211402_P01_WALL-SKIN-BACK-LOWER-B2_CAD (Autodesk Fusion 360 design; units mm, degrees)
part number: 2026-11-02-10-36-47-866
description: WALL - SKIN - BACK LOWER - B2 | Vách hậu - tấm ốp alu dưới phải | P01
part number: 211402
Autodesk Fusion 360 part; units mm, degrees
ref_plane "WorkPlane1" through (0, 0, 112.26) normal (0, 0, 1) x (1, 0, 0) in component "211402 WALL - SKIN - BACK LOWER - B2"
sketch "SKETCH - SKIN PLATE" plane through (0, 0, 112.26) normal (0, 0, 1) x (1, 0, 0) in component "211402 WALL - SKIN - BACK LOWER - B2"
  line L0 (1.13, 847) -> (1201.74, 847)
  line L1 (1201.74, 847) -> (1201.74, 850)
  line L2 (1201.74, 850) -> (1.13, 850)
  line L3 (1.13, 850) -> (1.13, 847)
  dimension "d218" = 1200.61
  dimension "d219" = 3
  dimension "d220" = 1.13
  dimension "d221" = 847
  constraint horizontal L0
  constraint vertical L1
  constraint horizontal L2
  constraint vertical L3
  measures "d218" horizontal distance of L0.start L0.end
  measures "d219" vertical distance of L0.start L2.end
  measures "d220" horizontal distance of origin L0.start
  measures "d221" vertical distance of origin L0.start
extrude "EXTRUDE - SKIN PLATE" add sketch "SKETCH - SKIN PLATE" along normal blind 1118.61 in component "211402 WALL - SKIN - BACK LOWER - B2"
ref_plane "WorkPlane2" through (0, 850, 0) normal (0, 1, 0) x (0, 0, 1) in component "211402 WALL - SKIN - BACK LOWER - B2"
sketch "HOLE CENTRE - SKIN MAINS INLET" plane through (0, 850, 0) normal (0, 1, 0) x (1, 0, 0) in component "211402 WALL - SKIN - BACK LOWER - B2"
  point P0 (120, -313)
  dimension "d226" = 120
  dimension "d227" = 313
  measures "d226" horizontal distance of origin P0
  measures "d227" vertical distance of origin P0
hole "HOLE - SKIN MAINS INLET" at (120, 850, 313) direction (0, -1, 0) diameter 24 depth 4 tip angle 118 in component "211402 WALL - SKIN - BACK LOWER - B2"
ref_plane "WorkPlane3" through (0, 850, 0) normal (0, 1, 0) x (0, 0, 1) in component "211402 WALL - SKIN - BACK LOWER - B2"
sketch "HOLE CENTRE - SKIN MAINS INLET SCREW 1" plane through (0, 850, 0) normal (0, 1, 0) x (1, 0, 0) in component "211402 WALL - SKIN - BACK LOWER - B2"
  point P0 (129.5, -325)
  dimension "d233" = 129.5
  dimension "d234" = 325
  measures "d233" horizontal distance of origin P0
  measures "d234" vertical distance of origin P0
hole "HOLE - SKIN MAINS INLET SCREW 1" at (129.5, 850, 325) direction (0, -1, 0) diameter 3.2 depth 4 tip angle 118 in component "211402 WALL - SKIN - BACK LOWER - B2"
ref_plane "WorkPlane4" through (0, 850, 0) normal (0, 1, 0) x (0, 0, 1) in component "211402 WALL - SKIN - BACK LOWER - B2"
sketch "HOLE CENTRE - SKIN MAINS INLET SCREW 2" plane through (0, 850, 0) normal (0, 1, 0) x (1, 0, 0) in component "211402 WALL - SKIN - BACK LOWER - B2"
  point P0 (110.5, -301)
  dimension "d240" = 110.5
  dimension "d241" = 301
  measures "d240" horizontal distance of origin P0
  measures "d241" vertical distance of origin P0
hole "HOLE - SKIN MAINS INLET SCREW 2" at (110.5, 850, 301) direction (0, -1, 0) diameter 3.2 depth 4 tip angle 118 in component "211402 WALL - SKIN - BACK LOWER - B2"
ref_plane "WorkPlane5" through (0, 850, 0) normal (0, 1, 0) x (0, 0, 1) in component "211402 WALL - SKIN - BACK LOWER - B2"
sketch "HOLE CENTRE - SKIN LAN FEED-THROUGH" plane through (0, 850, 0) normal (0, 1, 0) x (1, 0, 0) in component "211402 WALL - SKIN - BACK LOWER - B2"
  point P0 (170, -375)
  dimension "d247" = 170
  dimension "d248" = 375
  measures "d247" horizontal distance of origin P0
  measures "d248" vertical distance of origin P0
hole "HOLE - SKIN LAN FEED-THROUGH" at (170, 850, 375) direction (0, -1, 0) diameter 24 depth 4 tip angle 118 in component "211402 WALL - SKIN - BACK LOWER - B2"
ref_plane "WorkPlane6" through (0, 850, 0) normal (0, 1, 0) x (0, 0, 1) in component "211402 WALL - SKIN - BACK LOWER - B2"
sketch "HOLE CENTRE - SKIN LAN FEED-THROUGH SCREW 1" plane through (0, 850, 0) normal (0, 1, 0) x (1, 0, 0) in component "211402 WALL - SKIN - BACK LOWER - B2"
  point P0 (179.5, -387)
  dimension "d254" = 179.5
  dimension "d255" = 387
  measures "d254" horizontal distance of origin P0
  measures "d255" vertical distance of origin P0
hole "HOLE - SKIN LAN FEED-THROUGH SCREW 1" at (179.5, 850, 387) direction (0, -1, 0) diameter 3.2 depth 4 tip angle 118 in component "211402 WALL - SKIN - BACK LOWER - B2"
ref_plane "WorkPlane7" through (0, 850, 0) normal (0, 1, 0) x (0, 0, 1) in component "211402 WALL - SKIN - BACK LOWER - B2"
sketch "HOLE CENTRE - SKIN LAN FEED-THROUGH SCREW 2" plane through (0, 850, 0) normal (0, 1, 0) x (1, 0, 0) in component "211402 WALL - SKIN - BACK LOWER - B2"
  point P0 (160.5, -363)
  dimension "pod_w_Ref" = 2500
  dimension "pod_d_Ref" = 1700
  dimension "pod_h_Ref" = 2400
  dimension "glide_h_Ref" = 10
  dimension "band_h_Ref" = 100
  dimension "outer_t_Ref" = 46
  dimension "cav_gap_Ref" = 4
  dimension "cass_t_Ref" = 34
  dimension "stack_t_Ref" = 84
  dimension "lin_gap_Ref" = 4
  dimension "seam_gap_Ref" = 2.26
  dimension "wall_z0_Ref" = 110
  dimension "panel_z0_Ref" = 112.26
  dimension "back_oh_Ref" = 2239.48
  dimension "back_ph_Ref" = 1118.61
  dimension "half_pw_Ref" = 1200.61
  dimension "skin_t_Ref" = 3
  dimension "bond_t_Ref" = 3
  dimension "frame_t_Ref" = 40
  dimension "close_gap_Ref" = 5.5
  dimension "half_fw_Ref" = 1198.99
  dimension "bolt_edge_inset_Ref" = 220
  dimension "spigot_inset_Ref" = 100
  dimension "pod_w" = 2500
  dimension "pod_d" = 1700
  dimension "pod_h" = 2400
  dimension "panel_z0" = 112.26
  dimension "back_ph" = 1118.61
  dimension "back_oh" = 2239.48
  dimension "half_pw" = 1200.61
  dimension "half_fw" = 1198.99
  dimension "close_gap" = 5.5
  dimension "stack_t" = 84
  dimension "outer_t" = 46
  dimension "cass_t" = 34
  dimension "lin_gap" = 4
  dimension "seam_gap" = 2.26
  dimension "skin_t" = 3
  dimension "bond_t" = 3
  dimension "bolt_edge_inset" = 220
  dimension "spigot_inset" = 100
  dimension "tube_w" = 20
  dimension "tube_d" = 40
  dimension "stud_t" = 0.8
  dimension "plate_t" = 2
  dimension "stile_pitch_max" = 300
  dimension "skin_setback" = 0
  dimension "fill_t" = 40
  dimension "bolt_d" = 7
  dimension "access_d" = 19
  dimension "bolt_line_y" = 824
  dimension "rivnut_d" = 10
  dimension "spigot_d" = 8.5
  dimension "spigot_edge" = 100
  dimension "bolt_edge" = 220
  dimension "pocket_w" = 60
  dimension "felt_t" = 9
  dimension "tray_t" = 0.5
  dimension "tray_h" = 34
  dimension "lip_w" = 12
  dimension "bend_r" = 0.5
  dimension "felt_c" = 1
  dimension "gap_h" = 24
  dimension "clip_zone_h" = 60
  dimension "clip_zone_dz" = 100
  dimension "stopw_od" = 20
  dimension "stopw_id" = 10.5
  dimension "stopw_t" = 1.5
  dimension "rivnut_head_d" = 12.95
  dimension "rivnut_head_t" = 0.76
  dimension "rivnut_body_d" = 9.91
  dimension "rivnut_len" = 9.65
  dimension "m6_d" = 6
  dimension "spigot_pin_d" = 8
  dimension "spigot_proud" = 8
  dimension "spigot_slot" = 14
  dimension "tube_t" = 1
  dimension "lead_in" = 1
  dimension "pnl_len" = 1200.61
  dimension "frm_len" = 1198.99
  dimension "pnl_h" = 1118.61
  dimension "frm_h" = 1118.61
  dimension "top_h" = 20
  dimension "stile_pitch" = 294.7475
  dimension "stile_len" = 1078.61
  dimension "len_bolt_pitch" = 252.9967
  dimension "side_jnt_pitch" = 339.305
  dimension "cass_len" = 1164.87
  dimension "cass_h" = 1118.61
  dimension "el_pu_x0" = 95
  dimension "el_pu_h" = 260
  dimension "el_pu_zc" = 1000
  dimension "el_pu_clr" = 4
  dimension "el_cut_x0" = 91
  dimension "el_cut_z0" = 866
  dimension "el_cut_z1" = 1134
  dimension "el_inlet_x" = 120
  dimension "el_inlet_z" = 313
  dimension "el_lan_z" = 375
  dimension "el_inlet_d" = 24
  dimension "el_rn_xu1" = 110
  dimension "el_rn_xu2" = 376
  dimension "el_rn_xl1" = 160
  dimension "el_rn_xl2" = 376
  dimension "el_ps_mains_x" = 127
  dimension "el_ps_mains_db" = 15.9
  dimension "el_ps_mains_dt" = 20
  dimension "el_ps_lan_x" = 207
  dimension "el_ps_lan_db" = 11.1
  dimension "el_ps_lan_dt" = 14
  dimension "el_lan_x" = 170
  dimension "el_box_l" = 54
  dimension "el_box_r" = 28
  dimension "el_box_h" = 34
  dimension "el_jack_h" = 16
  dimension "el_ch_m_x1" = 100
  dimension "el_ch_jog_z" = 750
  dimension "el_ch_jog_x1" = 137
  dimension "el_ch_l_w" = 16
  dimension "el_ch_l_band" = 49
  dimension "el_scr_d" = 3.2
  dimension "el_scr_dx" = 9.5
  dimension "el_scr_dz" = 12
  dimension "xm_z0" = 849.24
  dimension "xm_z1" = 1150.76
  dimension "clip_top_dz" = 50.055
  dimension "ledge_t" = 1.5
  dimension "ledge_r" = 1.5
  dimension "ledge_out" = 28
  dimension "ledge_up" = 18
  dimension "ledge_pad_t" = 2.31
  dimension "ledge_pad_w" = 18
  dimension "ledge_end" = 5
  dimension "ledge_len" = 1154.87
  dimension "ledge_rivet_d" = 3.3
  dimension "ledge_rivet_e" = 40
  dimension "ledge_rivet_z" = 9
  dimension "ledge_rivet_pitch" = 214.974
  dimension "rivet_d" = 3.2
  dimension "rivet_head_d" = 6.7
  dimension "rivet_csk_angle" = 120
  dimension "rivet_head_t" = 1.0104
  dimension "ledge_csk_d" = 6.7
  dimension "rivet_len" = 8
  dimension "d261" = 160.5
  dimension "d262" = 363
  measures "d261" horizontal distance of origin P0
  measures "d262" vertical distance of origin P0
hole "HOLE - SKIN LAN FEED-THROUGH SCREW 2" at (160.5, 850, 363) direction (0, -1, 0) diameter 3.2 depth 4 tip angle 118 in component "211402 WALL - SKIN - BACK LOWER - B2"
component "211402 WALL - SKIN - BACK LOWER - B2" placed x (1, 0, 0) y (0, 1, 0) z (0, 0, 1) at (0, 0, 0)
equation "pod_w_Ref = 2500 mm" comment "DECIDED: D-01; conventions s4 (X = +-1250)"
equation "pod_d_Ref = 1700 mm" comment "DECIDED: D-01; conventions s4 (Y = +-850)"
equation "pod_h_Ref = 2400 mm" comment "DECIDED: D-21 (room floor to roof skin top)"
equation "glide_h_Ref = 10 mm" comment "ASSUMPTION: layout study inputs.py glide_h"
equation "band_h_Ref = 100 mm" comment "SOURCE: layout study B1 list B-BAND 100x40; inputs.py base_h"
equation "outer_t_Ref = skin_t_Ref + bond_t_Ref + frame_t_Ref" comment "DECIDED: PM ruling 2026-10-31: ACP 3 + bond line 3 + frame 40, walls and ceiling (was 43)"
equation "cav_gap_Ref = 4 mm" comment "DECIDED: D-16, D-42: the gap between the outer panel and the lining cassette in the wall and ceiling stack"
equation "cass_t_Ref = 34 mm" comment "SOURCE: layout study B1 final list L-CASS 34 (tray + 25 gap + felt 9)"
equation "stack_t_Ref = outer_t_Ref + cav_gap_Ref + cass_t_Ref" comment "CALCULATION: D-16, D-42 stack, walls and ceiling: outer panel + cavity gap + cassette (PM ruling 2026-10-31 on outer_t)"
equation "lin_gap_Ref = 4 mm" comment "ASSUMPTION: PM ruling pass C: gap above the upper side linings so they stay floating (= the 4 mm stack gap)"
equation "seam_gap_Ref = 2.26 mm" comment "DECIDED: PM ruling 2026-10-31 (Mechanical Checker F-001, F-005): the Joints Engineer's 2.26 mm at all nine site seam types, set by a metal stop (1.5 stop washer + 0.76 rivnut head; joints register section 2.8)"
equation "wall_z0_Ref = glide_h_Ref + band_h_Ref" comment "CALCULATION: base band top: glides + band"
equation "panel_z0_Ref = wall_z0_Ref + seam_gap_Ref" comment "CALCULATION: walls stand one seam_gap above the band top (joints register 2.8, IF-01)"
equation "back_oh_Ref = pod_h_Ref - outer_t_Ref - seam_gap_Ref - panel_z0_Ref" comment "CALCULATION: PM ruling 2026-10-31 (pass D, F-004): the back outer frames run up to the ceiling frame (pod_h - outer_t), less the seam_gap under it, closing the slot at the back top edge"
equation "back_ph_Ref = ( back_oh_Ref - seam_gap_Ref ) / 2" comment "CALCULATION: D-23: 4 sheets on the back, two equal rows with one seam_gap between them (joints register 2.8); the lower back linings match the lower row, as on the side walls"
equation "half_pw_Ref = ( pod_w_Ref - 2 * outer_t_Ref - 3 * seam_gap_Ref ) / 2" comment "CALCULATION: SKIN width of each back and ceiling panel: two skins and three seam_gap seams between the side frames (F-001, joints register 2.8)"
equation "n_base_bolt_Ref = 4" comment "DECIDED: PM ruling 2026-10-31, J-BASE-01: bolts per panel along the band, evenly spaced"
equation "skin_t_Ref = 3 mm" comment "DECIDED: ACP skin, walls and ceiling (D-16; PM ruling 2026-10-31 on outer_t)"
equation "bond_t_Ref = 3 mm" comment "DECIDED: bond line between the ACP and the frame (PM ruling 2026-10-31 on outer_t)"
equation "frame_t_Ref = 40 mm" comment "DECIDED: aluminium frame tube depth, walls and ceiling (PM ruling 2026-10-31 on outer_t)"
equation "close_gap_Ref = 5.5 mm" comment "DECIDED: PM ruling 2026-10-31 (joints register, F-011/F-012): frame gap at the closing seams B1-B2, B3-B4 and C1-C2, which have no hard stop (slotted holes, thicker gasket)"
equation "half_fw_Ref = ( pod_w_Ref - 2 * outer_t_Ref - 2 * seam_gap_Ref - close_gap_Ref ) / 2" comment "CALCULATION: FRAME width of each back and ceiling panel: the skins overhang their frames by half_pw - half_fw at the closing seam (PM ruling 2026-10-31)"
equation "bolt_edge_inset_Ref = 220 mm" comment "DECIDED: PM ruling 2026-10-31: on every bolted edge the end bolts sit this far in from each panel end (the FRAME end, where the bolts go), the rest evenly spaced"
equation "spigot_inset_Ref = 100 mm" comment "DECIDED: PM ruling 2026-10-31: locating spigots this far in from each panel end (round hole at one end, slot at the other)"
equation "pod_w = pod_w_Ref" comment "LINKED: pod_w_Ref, derived from 100000_P04_POD-SKELETON_CAD v6 (skeleton is the single source)"
equation "pod_d = pod_d_Ref" comment "LINKED: pod_d_Ref, derived from 100000_P04_POD-SKELETON_CAD v6 (skeleton is the single source)"
equation "pod_h = pod_h_Ref" comment "LINKED: pod_h_Ref, derived from 100000_P04_POD-SKELETON_CAD v6 (skeleton is the single source)"
equation "panel_z0 = panel_z0_Ref" comment "LINKED: panel_z0_Ref, derived from 100000_P04_POD-SKELETON_CAD v6 (skeleton is the single source)"
equation "back_ph = back_ph_Ref" comment "LINKED: back_ph_Ref, derived from 100000_P04_POD-SKELETON_CAD v6 (skeleton is the single source)"
equation "back_oh = back_oh_Ref" comment "LINKED: back_oh_Ref, derived from 100000_P04_POD-SKELETON_CAD v6 (skeleton is the single source)"
equation "half_pw = half_pw_Ref" comment "LINKED: half_pw_Ref, derived from 100000_P04_POD-SKELETON_CAD v6 (skeleton is the single source)"
equation "half_fw = half_fw_Ref" comment "LINKED: half_fw_Ref, derived from 100000_P04_POD-SKELETON_CAD v6 (skeleton is the single source)"
equation "close_gap = close_gap_Ref" comment "LINKED: close_gap_Ref, derived from 100000_P04_POD-SKELETON_CAD v6 (skeleton is the single source)"
equation "stack_t = stack_t_Ref" comment "LINKED: stack_t_Ref, derived from 100000_P04_POD-SKELETON_CAD v6 (skeleton is the single source)"
equation "outer_t = outer_t_Ref" comment "LINKED: outer_t_Ref, derived from 100000_P04_POD-SKELETON_CAD v6 (skeleton is the single source)"
equation "cass_t = cass_t_Ref" comment "LINKED: cass_t_Ref, derived from 100000_P04_POD-SKELETON_CAD v6 (skeleton is the single source)"
equation "lin_gap = lin_gap_Ref" comment "LINKED: lin_gap_Ref, derived from 100000_P04_POD-SKELETON_CAD v6 (skeleton is the single source)"
equation "seam_gap = seam_gap_Ref" comment "LINKED: seam_gap_Ref, derived from 100000_P04_POD-SKELETON_CAD v6 (skeleton is the single source)"
equation "skin_t = skin_t_Ref" comment "LINKED: skin_t_Ref, derived from 100000_P04_POD-SKELETON_CAD v6 (skeleton is the single source)"
equation "bond_t = bond_t_Ref" comment "LINKED: bond_t_Ref, derived from 100000_P04_POD-SKELETON_CAD v6 (skeleton is the single source)"
equation "bolt_edge_inset = bolt_edge_inset_Ref" comment "LINKED: bolt_edge_inset_Ref, derived from 100000_P04_POD-SKELETON_CAD v6 (skeleton is the single source)"
equation "spigot_inset = spigot_inset_Ref" comment "LINKED: spigot_inset_Ref, derived from 100000_P04_POD-SKELETON_CAD v6 (skeleton is the single source)"
equation "n_base_bolt = n_base_bolt_Ref" comment "LINKED: n_base_bolt_Ref, derived from 100000_P04_POD-SKELETON_CAD v6 (skeleton is the single source)"
equation "tube_w = 20 mm" comment "CONFIRMED: D-34, D-54, kept by D-131 (the same outside sections in welded, galvanized steel box tube): 20 x 40; the 20 mm face carries the skin, so the 40 mm runs through the wall (outer_t = ACP 3 + frame 40)"
equation "tube_d = outer_t - skin_t - bond_t" comment "CALCULATION: frame depth = outer panel 46 - skin 3 - bond 3 = 40 (D-34)"
equation "stud_t = 0.8 mm" comment "SOURCE: the same: the studs at 0.8 (no rivnut, only the skin's bond line)"
equation "plate_t = 2 mm" comment "SOURCE: the Joints Engineer's corner detail (2026-11-01 05:05): a 2 mm steel plate welded into each mitre, the members cut back so it fits, centred on the old mitre line"
equation "stile_pitch_max = 300 mm" comment "CONFIRMED: PM ruling 2026-11-01 (D-131 sample): the ACP flexes 2 mm or less under a 100 N push at a bay's centre, edges simply supported (make_acp_spans.py), so members about 300 apart; it was 400 (D-16, D-34)"
equation "skin_setback = 0 mm" comment "ASSUMPTION: skin edge set back from the frame's top and bottom edges: 0, so the outside reveal equals the 2.26 seam gap (D-23: crisp, aligned reveals; joints register 2.8 leaves the setback to the WALL drawing)"
equation "fill_t = tube_d" comment "CALCULATION: 40 mm PET fill fills the frame depth (D-34; layout study 40 mm)"
equation "bolt_d = 7 mm" comment "CONFIRMED: PM ruling on F-009: bolt holes 7.0 (0.51 float), position tolerance 0.4 (+-0.2) from the spigot hole, CNC or drill jig (joints register FR-02)"
equation "access_d = 19 mm" comment "CALCULATION: register FR-03: passes the 18 mm head washer (ISO 7093-1, R-J10), the M6 head and the 5 mm key; holds the grommet retainer (H-02)"
equation "bolt_line_y = pod_d / 2 - skin_t - bond_t - tube_d / 2" comment "CONFIRMED: J-WALL-02 bolt line on the back panel's tube centre, Y 824 (joints register R-J15, FR-07)"
equation "rivnut_d = 10 mm" comment "CONFIRMED: D-163 (the Lead's ruling, 2026-11-01): Sherex CAL2-610-4.2 in a round drilled hole Ø10.00 +0.10/0, inside the maker's 10.00 +0.15/-0.0 (Sherex drawing CAL2-610-4.2 rev B, note 2) so the bolt-hole stack ST-03 stays positive; T06's spin-out test confirms it"
equation "spigot_d = 8.5 mm" comment "ASSUMPTION: register FR-05: hole for the 8 mm locating spigot H-05"
equation "spigot_edge = spigot_inset" comment "CALCULATION: the skeleton's spigot_inset: spigots 100 from each end of the edge (PM ruling 2026-10-31, R-J13)"
equation "bolt_edge = bolt_edge_inset" comment "CALCULATION: the skeleton's bolt_edge_inset: end bolts 220 in from the panel's ends, evenly spaced, every bolt 30 or more from any stile (PM ruling 2026-10-31, R-J14)"
equation "pocket_w = 60 mm" comment "ASSUMPTION: register FR-10: fill left out 60 x 60 next to each bolt for the key"
equation "felt_t = 9 mm" comment "SOURCE: plan VT03-PET 9 mm PET felt; HW-SEL A3; D-31 (the factory's felt)"
equation "tray_t = 0.5 mm" comment "CONFIRMED: D-37: galvanised steel tray 0.5 mm"
equation "tray_h = cass_t" comment "CONFIRMED: PM ruling 2026-10-31 (WALL group, option 1): the wall cassettes use the ceiling's tray, returns the full cassette depth (34) turned in as lips that hold the felt, no ribs; settles H09 for the walls"
equation "lip_w = 12 mm" comment "CONFIRMED: PM ruling 2026-10-31 (WALL group, option 1): 12 mm lips hold the felt edge"
equation "bend_r = tray_t" comment "ASSUMPTION: inside bend radius 1 x t for 0.5 mm DX51D (the sheet metal rule's bend radius is its Thickness); the factory's tooling sets it (guideline 9)"
equation "felt_c = 1 mm" comment "ASSUMPTION: felt edge clearance inside the returns, as the ceiling cassette"
equation "gap_h = tray_h - felt_t - 2 * tray_t" comment "CALCULATION: air gap between the tray base and the felt (24): the acoustic gap (D-17) and the cable path (D-26)"
equation "clip_zone_h = 60 mm" comment "ASSUMPTION: height of each reserved clip zone (H03: no clip named)"
equation "clip_zone_dz = 100 mm" comment "ASSUMPTION: clip zone centre from the cassette's top and bottom edges (H03)"
equation "stopw_od = 20 mm" comment "SOURCE: joints register H-08: stop washer Ø10.5 x Ø20 x 1.5 (PROPOSED part)"
equation "stopw_id = 10.5 mm" comment "SOURCE: joints register H-08"
equation "stopw_t = 1.5 mm" comment "SOURCE: joints register H-08: rivnut head 0.76 + washer 1.5 = the 2.26 stop (R-J5)"
equation "rivnut_head_d = 12.95 mm" comment "SOURCE: Sherex CAL2-610-4.2 rev B: flange Ø12.45 to 12.95, the largest modelled (D-163)"
equation "rivnut_head_t = 0.76 mm" comment "SOURCE: Sherex CAL2-610-4.2 rev B: flange 0.68 to 0.84, its middle; with the 1.5 stop washer the 2.26 stop (R-J5), as before (D-163)"
equation "rivnut_body_d = 9.91 mm" comment "SOURCE: Sherex CAL2-610-4.2 rev B: knurled body Ø9.91 max (D-163)"
equation "rivnut_len = 9.65 mm" comment "SOURCE: Sherex CAL2-610-4.2 rev B, note 3: installed length 9.65 max under the flange (14.35 to 15.11 before setting); the bulge inside the tube is not modelled (D-163)"
equation "m6_d = 6 mm" comment "CALCULATION: M6 threads shown at their 6 mm major diameter (no modelled thread)"
equation "spigot_pin_d = 8 mm" comment "SOURCE: joints register H-05: Ø8 stainless pin; the part itself is Joints' 831001 STEP, placed as it is (F-189)"
equation "spigot_proud = 8 mm" comment "SOURCE: joints register H-05 and Joints' README: the pin's top 8.00 above the tube face (Z 7.24 above its origin on the rivnut head)"
equation "spigot_slot = 14 mm" comment "ASSUMPTION: register FR-05: the back panels' slot for the second spigot (D-167 lengthens the side panels' only)"
equation "tube_t = 1.0 mm" comment "SOURCE: the Joints Engineer's gauges for D-131 (2026-11-01): a back panel's perimeter members (rails, outer and centre stiles) at 1.0; the studs 0.8"
equation "lead_in = 1 mm" comment "SOURCE: joints register 2.10 (R-J9): 1 x 45 degree lead-in on the top edge of each closing-seam face, so the panel beside it drops in past it without catching the bulb seal"
equation "pnl_len = half_pw" comment "CALCULATION: skeleton half_pw: the back panel's skin width (1200.61 on P04)"
equation "frm_len = half_fw" comment "CALCULATION: the skeleton's half_fw, 1198.99: the frame stops close_gap / 2 from X 0 and 1.62 short of its skin (R-J16)"
equation "pnl_h = back_ph" comment "CALCULATION: skeleton back row height (1118.61 on P04)"
equation "frm_h = pnl_h" comment "CALCULATION: the frame fills the row height; the seam gaps are outside it (P04)"
equation "top_h = tube_w" comment "CALCULATION: the back panels' top rails stay 20 x 40 (the ceiling's back member is the 40 x 40, R-J3)"
equation "stile_n_mid = 3" comment "CALCULATION: PM ruling 2026-11-01 (D-135): 3 studs on a back panel, so the skin flexes 1.99 mm under a 100 N push at 274.75 clear (make_acp_spans.py); a fixed count (the studs are copies held by joints), the pitch follows the width, and the build refuses a pitch over stile_pitch_max"
equation "stile_pitch = ( frm_len - tube_w ) / ( stile_n_mid + 1 )" comment "CALCULATION: equal stile pitch, centre to centre"
equation "stile_len = frm_h - 2 * tube_w" comment "CALCULATION: studs between the rails (square ends, welded T joints, D-131); the perimeter stiles run the full height, mitred (D-117) and welded"
equation "n_len_bolt = n_base_bolt" comment "CALCULATION: the skeleton's n_base_bolt (4): also on the horizontal seam and the ceiling back edge (register 2.9; the skeleton's n_ceil_back_bolt 3 is an old assumption, flagged)"
equation "len_bolt_pitch = ( frm_len - 2 * bolt_edge ) / ( n_len_bolt - 1 )" comment "CALCULATION: 253.00 on P04: 220, 473.00, 725.99, 978.99 from the frame's ends (register 2.9; the skeleton's back_base_pitch uses the 1200.61 skin and gives 253.54, flagged to its owner)"
equation "n_side_jnt = 3" comment "SOURCE: 3 bolts on the back corner and on the closing seam (register 2.9)"
equation "side_jnt_pitch = ( pnl_h - 2 * bolt_edge ) / ( n_side_jnt - 1 )" comment "CALCULATION: 339.31 on P04: 220, 559.31, 898.61 up the 1118.61 edge (register 2.9)"
equation "cass_len = pod_w / 2 - stack_t - seam_gap / 2" comment "ASSUMPTION: PROPOSED (WALL): from the side lining's face to seam_gap / 2 short of X 0. Each cassette hangs on its own panel's frame and the closing seam moves (5.2 to 5.8, register 2.11), so the skeleton's touching edges at X 0 could clash; a 2.26 gap matches the skin seam above it (R-J16) and takes the H-14 edge seal"
equation "cass_h = pnl_h" comment "CALCULATION: lower: the row height; upper: up to lin_gap under the ceiling frame, floating (D-57; P04)"
equation "el_pu_x0 = 95 mm" comment "ASSUMPTION: ELECTRICAL P01 (electrical_model.py, PR #64) pu_x0: the power unit's left side, clear of the closing seam member and its pin-bolt pocket"
equation "el_pu_h = 260 mm" comment "SOURCE: ELECTRICAL's final unit size (PM 2026-10-31 20:38 UTC): Z 870 to 1130"
equation "el_pu_zc = 1000 mm" comment "CONFIRMED: ELECTRICAL P01 (electrical_model.py, PR #64) pu_zc: the socket and LAN at the ledge height (D-70)"
equation "el_pu_clr = 4 mm" comment "ASSUMPTION: ELECTRICAL P01 (electrical_model.py, PR #64) pu_clr: the gap round the frame-mounted unit, so the cassette stays floating (= cav_gap)"
equation "el_cut_x0 = el_pu_x0 - el_pu_clr" comment "CALCULATION: B2-CASS cut-out: its left return's inner face (X 91)"
equation "el_cut_z0 = el_pu_zc - el_pu_h / 2 - el_pu_clr" comment "CALCULATION: B2-CASS cut-out: its bottom return's inner face (Z 866)"
equation "el_cut_z1 = el_pu_zc + el_pu_h / 2 + el_pu_clr" comment "CALCULATION: ELECTRICAL P01 (electrical_model.py, PR #64) cut_z1: B2-CASS cut-out: its top return's inner face (Z 1134)"
equation "el_inlet_x = 120 mm" comment "ASSUMPTION: ELECTRICAL P01 (electrical_model.py, PR #64) inlet_x: the inlet column, just clear of the closing seam"
equation "el_inlet_z = 313 mm" comment "SOURCE: ELECTRICAL P01 (electrical_model.py, PR #64) inlet_z: v1's 'Power Jack' centre Z 298.3 + 15"
equation "el_lan_z = 375 mm" comment "SOURCE: ELECTRICAL P01 (electrical_model.py, PR #64) lan_z: v1's 'Jack LAN' centre Z 360 + 15"
equation "el_inlet_d = 24 mm" comment "SOURCE: ELECTRICAL P01 (electrical_model.py, PR #64) inlet_d: powerCON TRUE1 TOP cut-out 23.8, etherCON NE8FDP 24"
equation "el_rn_xu1 = 110 mm" comment "SOURCE: ELECTRICAL's B2 inputs (WALL group, 2026-11-01): the upper cross member's first unit rivnut, in its underside"
equation "el_rn_xu2 = 376 mm" comment "SOURCE: ELECTRICAL's B2 inputs (WALL group, 2026-11-01): the upper cross member's second unit rivnut, in its underside"
equation "el_rn_xl1 = 160 mm" comment "SOURCE: ELECTRICAL's B2 inputs (WALL group, 2026-11-01): the lower cross member's first unit rivnut, in its top (not 110: that clashed with the mains passage)"
equation "el_rn_xl2 = 376 mm" comment "SOURCE: ELECTRICAL's B2 inputs (WALL group, 2026-11-01): the lower cross member's second unit rivnut, in its top"
equation "el_ps_mains_x = 127 mm" comment "SOURCE: ELECTRICAL in WALL's group (2026-11-01 17:47 UTC): the mains cord's passage through the lower cross member, moved from X 113 so the unit's Ø15.9 entry keeps 2 diameters (31.8) from the free edge at its bottom wall's open corner"
equation "el_ps_mains_db = 15.9 mm" comment "SOURCE: ELECTRICAL's B2 inputs (WALL group, 2026-11-01): the mains passage in the member's bottom wall, for the Heyco SB 625-7 bushing snapped in from below"
equation "el_ps_mains_dt = 20 mm" comment "SOURCE: ELECTRICAL's B2 inputs (WALL group, 2026-11-01): the mains passage in the member's top wall, lined by the unit's own bushing from above"
equation "el_ps_lan_x = 207 mm" comment "SOURCE: ELECTRICAL's B2 inputs (WALL group, 2026-11-01): the LAN cable's passage through the lower cross member"
equation "el_ps_lan_db = 11.1 mm" comment "SOURCE: ELECTRICAL's B2 inputs (WALL group, 2026-11-01): the LAN passage in the member's bottom wall, for the Heyco SB 437-5 bushing snapped in from below"
equation "el_ps_lan_dt = 14 mm" comment "SOURCE: ELECTRICAL's B2 inputs (WALL group, 2026-11-01): the LAN passage in the member's top wall, lined by the unit's own bushing from above"
equation "el_lan_x = 170 mm" comment "SOURCE: ELECTRICAL's B2 inputs (WALL group, 2026-11-01): the LAN jack at X 170, Z 375, the same cut-out, turned 180°"
equation "el_box_l = 54 mm" comment "SOURCE: ELECTRICAL's B2 inputs (WALL group, 2026-11-01): the inlet's rear box and cord grip, X 66 to 148: 54 left of the inlet"
equation "el_box_r = 28 mm" comment "SOURCE: ELECTRICAL's B2 inputs (WALL group, 2026-11-01): the rear box 28 right of the inlet"
equation "el_box_h = 34 mm" comment "SOURCE: ELECTRICAL's B2 inputs (WALL group, 2026-11-01): the rear box Z 279 to 347: 34 each side of the inlet"
equation "el_jack_h = 16 mm" comment "SOURCE: ELECTRICAL's B2 inputs (WALL group, 2026-11-01): the jack's body X 154 to 186, Z 359 to 391: 16 round its centre"
equation "el_ch_m_x1 = 100 mm" comment "SOURCE: ELECTRICAL's B2 inputs (WALL group, 2026-11-01): the mains cord's channel up at X 80 to 100, 20 wide; WALL clears the fill from the centre stile to X 100 (no strip by its notches)"
equation "el_ch_jog_z = 750 mm" comment "SOURCE: ELECTRICAL in WALL's group (2026-11-01 18:05 UTC): the mains cord's jog over to its passage starts at Z 750, not 809, so its S-bend has about 70 of radius; the cord, Southwire's 105 °C SJEOOW 14/3 at 9.2, bends no tighter than 4 x its diameter, 37 (its maker's sheet, ELECTRICAL 18:28 UTC)"
equation "el_ch_jog_x1 = el_ps_mains_x + 10 mm" comment "SOURCE: ELECTRICAL in WALL's group (2026-11-01 17:47 UTC): the mains cord's jog ends 10 past its passage, at X 137"
equation "el_ch_l_w = 16 mm" comment "SOURCE: ELECTRICAL's B2 inputs (WALL group, 2026-11-01): the LAN cable's channel 16 wide, up from the jack's top"
equation "el_ch_l_band = 49 mm" comment "SOURCE: ELECTRICAL in WALL's group (2026-11-01 18:05 UTC): the LAN band along the jack's top, Z 391 to 440, not 407: the Cat6 bends no tighter than 4 x its diameter, 24, so it needs about 46 of height to move the 37 over to its riser"
equation "el_scr_d = 3.2 mm" comment "SOURCE: ELECTRICAL's B2 inputs (WALL group, 2026-11-01): each connector's two screw holes for M3 screws with nuts (Neutrik's own drawings: powerCON TRUE1 TOP NAC3MPX-TOP, etherCON NE8FDY-C6-B; D-133)"
equation "el_scr_dx = 9.5 mm" comment "SOURCE: ELECTRICAL's B2 inputs (WALL group, 2026-11-01): the screw holes on the diagonal, X +9.5 and -9.5 from the centre"
equation "el_scr_dz = 12 mm" comment "SOURCE: ELECTRICAL's B2 inputs (WALL group, 2026-11-01): the screw holes on the diagonal, Z +12 and -12 from the centre"
equation "xm_z0 = el_pu_zc - el_pu_h / 2 - rivnut_head_t - tube_w" comment "CALCULATION: the Lead's approval of WALL's B2 frame (2026-11-01): the lower cross member's bottom face; its top face a rivnut head under the unit, which sits on the rivnut heads (ELECTRICAL, 2026-11-01): Z 849.24"
equation "xm_z1 = el_pu_zc + el_pu_h / 2 + rivnut_head_t + tube_w" comment "CALCULATION: the Lead's approval of WALL's B2 frame (2026-11-01): the upper cross member's top face, its underside a rivnut head over the unit: Z 1150.76"
equation "clip_top_dz = top_h + ( back_ph - top_h - ( xm_z1 - panel_z0 ) ) / 2" comment "CALCULATION: the Lead's approval of WALL's B2 frame (2026-11-01): the top-front clip zone's centre from the cassette's top, at the middle of the stub above the unit (Z 1150.76 to 1210.87): 50.06"
equation "ledge_t = 1.5 mm" comment "CONFIRMED: the Lead's ledge ruling, 2026-11-01 (WALL's sizes, accepted): galvanized steel sheet, DX51D+Z (EN 10346), Z100; 1.5 (the Lead's ruling the same day) so each rivet's countersink is machined in the upright with land under it, the heads flush and the rail's hole plain: 0.40 clear of the tray at J-FRAME-01's worst case"
equation "ledge_r = ledge_t" comment "ASSUMPTION: inside bend radius 1 x t, as the trays (the sheet metal rule's)"
equation "ledge_out = 28 mm" comment "ASSUMPTION: the Lead's ledge ruling, 2026-11-01 (WALL's sizes, accepted): the leg from the rail's room face, under the tray's 34 deep bottom return; its tip 10 short of the lining's room face, out of sight"
equation "ledge_up = tube_w - 2 mm" comment "ASSUMPTION: the Lead's ledge ruling, 2026-11-01 (WALL's sizes, accepted): the upright reaches 2 under the bottom rail's top face"
equation "ledge_pad_t = 2.31 mm" comment "CALCULATION: Joints' pick (WALL group, 2026-11-01): Rogers PORON 4701-40, the 320 kg/m3 grade, 2.36 thick (a standard size), PSA one side, slit 18 wide; the ledge's 7.7 kPa squeezes it about 2%, to about 2.31, so the leg sits 2.31 under the frame's bottom and the cassette's bottom stays level with it (the foam is ±10% thick)"
equation "ledge_pad_w = 18 mm" comment "SOURCE: Joints' pick: the pad slit 18 wide, on the leg's flat past its bend"
equation "ledge_end = 5 mm" comment "ASSUMPTION: the Lead's ledge ruling, 2026-11-01 (WALL's sizes, accepted): the ledge's ends 5 inside the right-hand cassette's"
equation "ledge_len = abs(( ( pod_w / 2 - stack_t ) ) - ( seam_gap / 2 )) - 2 * ledge_end" comment "CALCULATION: the back cassette's width less 5 at each end: 1154.9; B1's and B2's the same, so they share 211801"
equation "ledge_rivet_d = 3.3 mm" comment "SOURCE: joints register H-47, KK2 (Wurth 51452328 and the ISO 15974 table): the hole for 838012, Ø3.3 in the upright and the rail"
equation "ledge_rivet_n = 6" comment "ASSUMPTION: the Lead's ledge ruling, 2026-11-01 (WALL's sizes, accepted): 6 rivets for the two cassettes' 20.2 kg, about 33 N each"
equation "ledge_rivet_e = 40 mm" comment "ASSUMPTION: the end rivets 40 in from the ledge's ends"
equation "ledge_rivet_z = tube_w / 2 - 1 mm" comment "CALCULATION: the rivet line 9 above the frame's bottom: 9.0 from the upright's top edge (2.8 x the Ø3.2 rivet) and the hole's edge 8.2 from the bend"
equation "ledge_rivet_pitch = ( ledge_len - 2 * ledge_rivet_e ) / ( ledge_rivet_n - 1 )" comment "CALCULATION: even, so the pattern is symmetric and the turned copy (RH) matches: one part"
equation "rivet_d = 3.2 mm" comment "SOURCE: joints register H-47, KK2 (Wurth 51452328 and the ISO 15974 table): 838012, closed end (D-166), countersunk, aluminium body with a steel mandrel, 3.2 x 8, grip 1.0 to 3.5 for the 1.5 + 1.2 = 2.7; shear 1100 N, tensile 1450 N"
equation "rivet_head_d = 6.7 mm" comment "SOURCE: joints register H-47, KK2 (Wurth 51452328 and the ISO 15974 table): the countersunk head Ø5.8 to 6.7, its largest"
equation "rivet_csk_angle = 120 deg" comment "SOURCE: joints register H-47, KK2 (Wurth 51452328 and the ISO 15974 table): the head's 120 degrees"
equation "rivet_head_t = ( rivet_head_d - rivet_d ) / 2 / tan(rivet_csk_angle / 2)" comment "CALCULATION: the head's cone: 1.01 deep for Ø6.7 at 120 (the standard allows 1.3 at most: a rim at most 0.3 proud still clears the tray by 0.1 at J-FRAME-01's worst case)"
equation "ledge_csk_d = rivet_head_d" comment "CALCULATION: the upright's machined countersink: Ø6.7 at the head's 120, the head's largest, so every head (Ø5.8 to 6.7) sits flush or under; 0.52 of the 1.5 upright stays under it at the Ø3.3 hole (a third of its thickness)"
equation "rivet_len = 8 mm" comment "SOURCE: joints register H-47, KK2 (Wurth 51452328 and the ISO 15974 table): 8 long overall (its envelope)"
equation "d216 = ( panel_z0 ) + skin_setback"
equation "d218 = ( seam_gap / 2 + half_pw ) - ( seam_gap / 2 )"
equation "d219 = ( pod_d / 2 ) - ( pod_d / 2 - skin_t )"
equation "d220 = abs(seam_gap / 2)"
equation "d221 = abs(pod_d / 2 - skin_t)"
equation "d222 = ( ( panel_z0 + back_ph ) - skin_setback ) - ( ( panel_z0 ) + skin_setback )"
equation "d224 = pod_d / 2"
equation "d226 = abs(el_inlet_x)"
equation "d227 = abs(el_inlet_z)"
equation "d228 = skin_t + 1 mm"
equation "d229 = el_inlet_d"
equation "d231 = pod_d / 2"
equation "d233 = abs(el_inlet_x + el_scr_dx)"
equation "d234 = abs(( el_inlet_z ) + el_scr_dz)"
equation "d235 = skin_t + 1 mm"
equation "d236 = el_scr_d"
equation "d238 = pod_d / 2"
equation "d240 = abs(el_inlet_x - el_scr_dx)"
equation "d241 = abs(( el_inlet_z ) - el_scr_dz)"
equation "d242 = skin_t + 1 mm"
equation "d243 = el_scr_d"
equation "d245 = pod_d / 2"
equation "d247 = abs(el_lan_x)"
equation "d248 = abs(el_lan_z)"
equation "d249 = skin_t + 1 mm"
equation "d250 = el_inlet_d"
equation "d252 = pod_d / 2"
equation "d254 = abs(el_lan_x + el_scr_dx)"
equation "d255 = abs(( el_lan_z ) + el_scr_dz)"
equation "d256 = skin_t + 1 mm"
equation "d257 = el_scr_d"
equation "d259 = pod_d / 2"
equation "d261 = abs(el_lan_x - el_scr_dx)"
equation "d262 = abs(( el_lan_z ) - el_scr_dz)"
equation "d263 = skin_t + 1 mm"
equation "d264 = el_scr_d"
named bodies: "SKIN - ACP 3, OVERHANGS THE FRAME 1.62 AT THE CLOSING SEAM"
